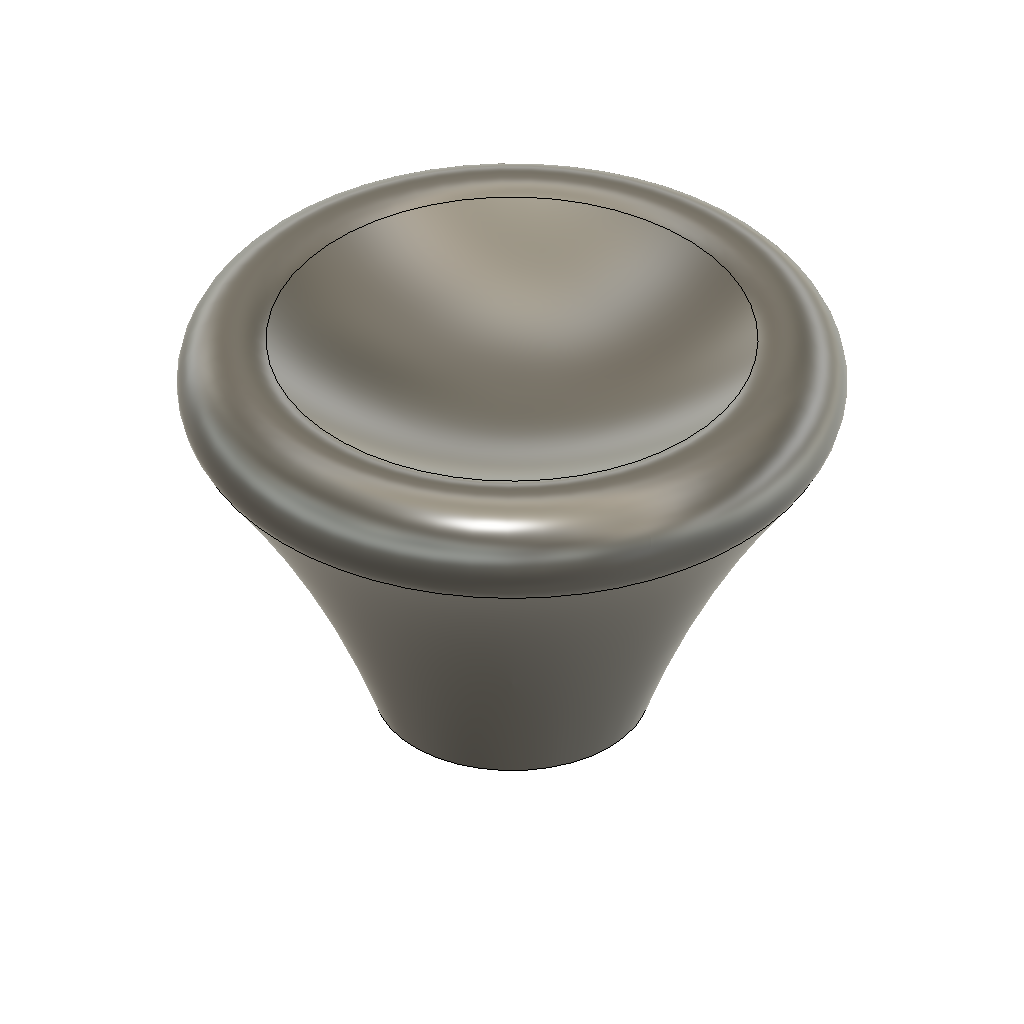
Finger Spin (Autodesk Fusion 360 design; units mm, degrees)
Autodesk Fusion 360 part; units mm, degrees
sketch "Sketch1" plane through (0, 0, 0) normal (0, 0, 1) x (1, 0, 0)
  line L0 (0, 8.2112) -> (0, 69.9728) construction
  line L1 (2.3, 0) -> (4, 0) construction
  line L2 (-17.5327, 15) -> (20.026, 15) construction
  arc A0 (9.3924, 9.94) -> (4, 0) centre (38.7944, -12.4432) ccw
  arc A1 (0, 10.7112) -> (7.1502, 12.5298) centre (0.1289, 25.1698) ccw
  line L3 (2.3, 0) -> (4, 0)
  arc A2 (9.3924, 9.94) -> (7.1502, 12.5298) centre (8, 11) ccw
  line L4 (0, 8.2112) -> (0, 10.7112)
  line L5 (2.3, 0) -> (2.3, 5.9112)
  line L6 (2.3, 5.9112) -> (0, 8.2112)
  line L7 (8, 11) -> (8, -0.0053) construction
  dimension "d1" = 4
  dimension "d2" = 15
  dimension "d4" = 2.3
  dimension "d5" = 45
  dimension "d7" = 8
  dimension "d9" = 1.75
  dimension "d10" = 2.5
  dimension "d11" = 5.9112
  dimension "d12" = 11
  constraint vertical L0
  constraint perpendicular L0 L1
  constraint perpendicular L0 L2
  constraint coincident L0 A1.start
  constraint tangent A1 A2
  constraint tangent A0 A2
  constraint perpendicular L1 L5
  constraint coincident A2.centre L7.start
  constraint perpendicular L2 L7
  constraint horizontal origin L1.start
  measures "d1" distance of origin L1.end
  measures "d2" distance of origin L2
  measures "d4" distance of L4 L5
  measures "d5" angle of L0 L6
  measures "d7" distance of L4 L7
  measures "d9" radius of A2
  measures "d10" distance of A1.start L0.start
  measures "d11" distance of L1.start L5.end
  measures "d12" vertical distance of origin A2.centre
revolve "Revolve2" add sketch "Sketch1" angle 360 about axis through (0, 8.2112, 0) along (0, 1, 0)
revolve "Revolve1" [suppressed]
sketch "Sketch2" plane through (0, 0, 0) normal (0, 0, 1) x (1, 0, 0)
named bodies: "finger spin"
